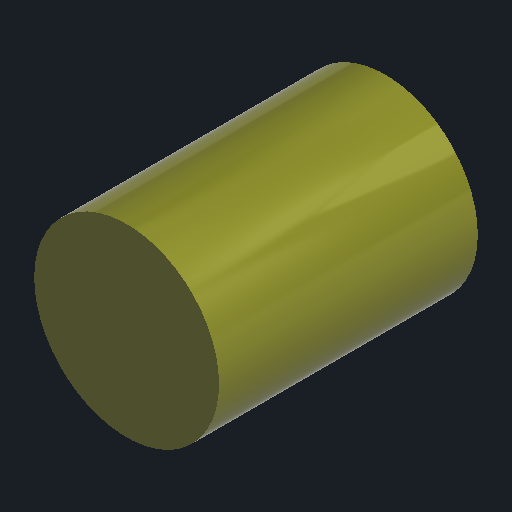
# Autodesk Inventor part: Engranaje_Recto_1a1_m1_Z20
Saved by Autodesk Inventor 2027.2 (Build 312334000, 334)
## iProperties
Part Number: Engranaje_Recto_1a1_m1_Z20
Material: Genérico
Document SubType Name: Modelado
Designer: Usuario
Appearance: Por defecto
Author: Usuario
Autodesk Inventor part; units mm, degrees
ref_plane "Plano YZ" through (0, 0, 0) normal (1, 0, 0) x (0, 1, 0)
ref_plane "Plano XZ" through (0, 0, 0) normal (0, 1, 0) x (-1, 0, 0)
ref_plane "Plano XY" through (0, 0, 0) normal (0, 0, 1) x (1, 0, 0)
sketch "Boceto1" plane through (0, 0, 0) normal (0, 0, 1) x (1, 0, 0)
  line L0 (8.7021, -0.9146) -> (10.9849, -0.5757)
  line L1 (10.9849, -0.5757) -> (10.9849, 0.5757)
  line L2 (10.9849, 0.5757) -> (8.7021, 0.9146)
  line L3 (8.7021, 0.9146) -> (8.5588, 1.8192)
  line L4 (8.5588, 1.8192) -> (10.6252, 2.847)
  line L5 (10.6252, 2.847) -> (10.2694, 3.942)
  line L6 (10.2694, 3.942) -> (7.9935, 3.5589)
  line L7 (7.9935, 3.5589) -> (7.5777, 4.375)
  line L8 (7.5777, 4.375) -> (9.2254, 5.991)
  line L9 (9.2254, 5.991) -> (8.5486, 6.9225)
  line L10 (8.5486, 6.9225) -> (6.5025, 5.8549)
  line L11 (6.5025, 5.8549) -> (5.8549, 6.5025)
  line L12 (5.8549, 6.5025) -> (6.9225, 8.5486)
  line L13 (6.9225, 8.5486) -> (5.991, 9.2254)
  line L14 (5.991, 9.2254) -> (4.375, 7.5777)
  line L15 (4.375, 7.5777) -> (3.5589, 7.9935)
  line L16 (3.5589, 7.9935) -> (3.942, 10.2694)
  line L17 (3.942, 10.2694) -> (2.847, 10.6252)
  line L18 (2.847, 10.6252) -> (1.8192, 8.5588)
  line L19 (1.8192, 8.5588) -> (0.9146, 8.7021)
  line L20 (0.9146, 8.7021) -> (0.5757, 10.9849)
  line L21 (0.5757, 10.9849) -> (-0.5757, 10.9849)
  line L22 (-0.5757, 10.9849) -> (-0.9146, 8.7021)
  line L23 (-0.9146, 8.7021) -> (-1.8192, 8.5588)
  line L24 (-1.8192, 8.5588) -> (-2.847, 10.6252)
  line L25 (-2.847, 10.6252) -> (-3.942, 10.2694)
  line L26 (-3.942, 10.2694) -> (-3.5589, 7.9935)
  line L27 (-3.5589, 7.9935) -> (-4.375, 7.5777)
  line L28 (-4.375, 7.5777) -> (-5.991, 9.2254)
  line L29 (-5.991, 9.2254) -> (-6.9225, 8.5486)
  line L30 (-6.9225, 8.5486) -> (-5.8549, 6.5025)
  line L31 (-5.8549, 6.5025) -> (-6.5025, 5.8549)
  line L32 (-6.5025, 5.8549) -> (-8.5486, 6.9225)
  line L33 (-8.5486, 6.9225) -> (-9.2254, 5.991)
  line L34 (-9.2254, 5.991) -> (-7.5777, 4.375)
  line L35 (-7.5777, 4.375) -> (-7.9935, 3.5589)
  line L36 (-7.9935, 3.5589) -> (-10.2694, 3.942)
  line L37 (-10.2694, 3.942) -> (-10.6252, 2.847)
  line L38 (-10.6252, 2.847) -> (-8.5588, 1.8192)
  line L39 (-8.5588, 1.8192) -> (-8.7021, 0.9146)
  line L40 (-8.7021, 0.9146) -> (-10.9849, 0.5757)
  line L41 (-10.9849, 0.5757) -> (-10.9849, -0.5757)
  line L42 (-10.9849, -0.5757) -> (-8.7021, -0.9146)
  line L43 (-8.7021, -0.9146) -> (-8.5588, -1.8192)
  line L44 (-8.5588, -1.8192) -> (-10.6252, -2.847)
  line L45 (-10.6252, -2.847) -> (-10.2694, -3.942)
  line L46 (-10.2694, -3.942) -> (-7.9935, -3.5589)
  line L47 (-7.9935, -3.5589) -> (-7.5777, -4.375)
  line L48 (-7.5777, -4.375) -> (-9.2254, -5.991)
  line L49 (-9.2254, -5.991) -> (-8.5486, -6.9225)
  line L50 (-8.5486, -6.9225) -> (-6.5025, -5.8549)
  line L51 (-6.5025, -5.8549) -> (-5.8549, -6.5025)
  line L52 (-5.8549, -6.5025) -> (-6.9225, -8.5486)
  line L53 (-6.9225, -8.5486) -> (-5.991, -9.2254)
  line L54 (-5.991, -9.2254) -> (-4.375, -7.5777)
  line L55 (-4.375, -7.5777) -> (-3.5589, -7.9935)
  line L56 (-3.5589, -7.9935) -> (-3.942, -10.2694)
  line L57 (-3.942, -10.2694) -> (-2.847, -10.6252)
  line L58 (-2.847, -10.6252) -> (-1.8192, -8.5588)
  line L59 (-1.8192, -8.5588) -> (-0.9146, -8.7021)
  line L60 (-0.9146, -8.7021) -> (-0.5757, -10.9849)
  line L61 (-0.5757, -10.9849) -> (0.5757, -10.9849)
  line L62 (0.5757, -10.9849) -> (0.9146, -8.7021)
  line L63 (0.9146, -8.7021) -> (1.8192, -8.5588)
  line L64 (1.8192, -8.5588) -> (2.847, -10.6252)
  line L65 (2.847, -10.6252) -> (3.942, -10.2694)
  line L66 (3.942, -10.2694) -> (3.5589, -7.9935)
  line L67 (3.5589, -7.9935) -> (4.375, -7.5777)
  line L68 (4.375, -7.5777) -> (5.991, -9.2254)
  line L69 (5.991, -9.2254) -> (6.9225, -8.5486)
  line L70 (6.9225, -8.5486) -> (5.8549, -6.5025)
  line L71 (5.8549, -6.5025) -> (6.5025, -5.8549)
  line L72 (6.5025, -5.8549) -> (8.5486, -6.9225)
  line L73 (8.5486, -6.9225) -> (9.2254, -5.991)
  line L74 (9.2254, -5.991) -> (7.5777, -4.375)
  line L75 (7.5777, -4.375) -> (7.9935, -3.5589)
  line L76 (7.9935, -3.5589) -> (10.2694, -3.942)
  line L77 (10.2694, -3.942) -> (10.6252, -2.847)
  line L78 (10.6252, -2.847) -> (8.5588, -1.8192)
  line L79 (8.5588, -1.8192) -> (8.7021, -0.9146)
  circle A0 centre (0, 0) radius 2.5
  constraints: 160 end point, 1 centre point
extrude "Extrusión1" add sketch "Boceto1" along normal blind 7 contours A0
